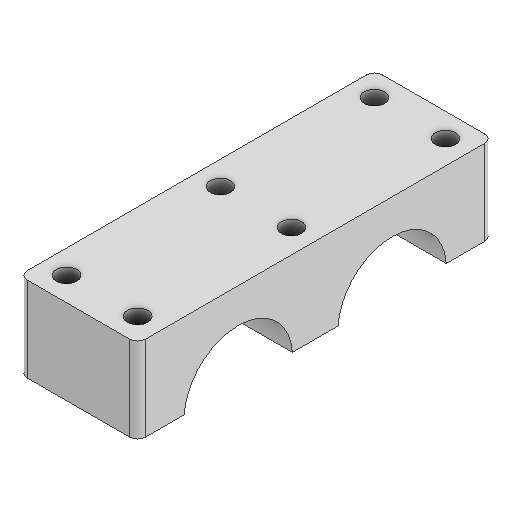
# Autodesk Inventor part: 3DP_PLA_A_Axis_Rotating_Stage_Fiberglass_pipes_mount_clamp
Saved by Autodesk Inventor 2027 (Build 310192060, 192F)
## iProperties
Created: 2026-01-07
Part Number: 3DP_PLA_A_Axis_Rotating_Stage_Fiberglass_pipes_mount_clamp
Material: Generic
Document SubType Name: Modeling
Designer: User
Density: 1 g/cm^3
Appearance: Default
Author: User
Autodesk Inventor part; units mm, degrees
ref_plane "YZ Plane" through (0, 0, 0) normal (1, 0, 0) x (0, 1, 0)
ref_plane "XZ Plane" through (0, 0, 0) normal (0, 1, 0) x (-1, 0, 0)
ref_plane "XY Plane" through (0, 0, 0) normal (0, 0, 1) x (1, 0, 0)
sketch "Sketch1" plane through (0, 0, 0) normal (0, 1, 0) x (-1, 0, 0)
  line L0 (15, 45) -> (-15, 45)
  line L1 (-15, 45) -> (-15, -45)
  line L2 (-15, -45) -> (15, -45)
  line L3 (15, -45) -> (15, 45)
  point P0 (0, 0)
  point P1 (9, 39)
  point P2 (-9, 39)
  point P3 (9, 0)
  point P4 (-9, 0)
  point P5 (9, -39)
  point P6 (-9, -39)
  dimension "d0" = 90
  dimension "d1" = 30
  dimension "d2" = 15
  dimension "d3" = 45
  dimension "d4" = 6
  dimension "d5" = 6
  dimension "d6" = 39
  dimension "d7" = 6
  dimension "d8" = 6
  constraints: 8 end point, 4 vertical alignment, 3 horizontal alignment, 2 parallel, 1 horizontal, 1 perpendicular
  measures "d0" distance between parallel lines of L2 L0
  measures "d1" distance between parallel lines of L1 L3
  measures "d2" distance from line of L3 point (0, 0)
  measures "d3" distance from line of L0 point (0, 0)
  measures "d4" distance from line of L0 point (-9, 39)
  measures "d5" distance from line of L2 point (-9, -39)
  measures "d6" distance of point (-9, 0) point (-9, 39)
  measures "d7" distance from line of L1 point (-9, 39)
  measures "d8" distance from line of L3 point (9, 39)
extrude "Extrusion1" add sketch "Sketch1" along normal blind 21.5
hole "Hole1" at (-9, 0, 39) at (9, 0, 39) at (-9, 0, 0) at (9, 0, 0) at (-9, 0, -39) at (9, 0, -39) direction (0, 1, 0) diameter 5.2 end through all
sketch "Sketch2" plane through (15, 0, 45) normal (1, 0, 0) x (0, 0, -1)
  line L0 (0, 0) -> (90, 0) projected
  line L1 (90, 0) -> (90, 21.5) projected
  line L2 (0, 21.5) -> (90, 21.5) projected
  line L3 (0, 0) -> (0, 21.5) projected
  circle A0 centre (25.5, -1) radius 13.75
  circle A1 centre (64.5, -1) radius 13.75
  line L4 (0, 0) -> (90, 0) projected
  point P0 (45, 0)
  point P1 (45, 0)
  point P2 (45, 0)
  point P3 (45, 0)
  dimension "d18" = 27.5
  dimension "d19" = 27.5
  dimension "d20" = 90
  dimension "d21" = 45
  dimension "d22" = 19.5
  dimension "d23" = 19.5
  dimension "d24" = 1
  constraints: 3 midpoint, 2 centre point, 1 horizontal alignment
  measures "d18" diameter of A0
  measures "d19" diameter of A1
  measures "d20" distance between parallel lines of L1 L3
  measures "d21" distance from line of point (45, 0) L3
  measures "d22" horizontal distance of point (45, 0) A0.centre
  measures "d23" horizontal distance of point (45, 0) A1.centre
  measures "d24" distance from line of L0 A0.centre
extrude "Extrusion2" cut sketch "Sketch2" against normal through all contours A0 L0 | L0 A0 | A1 L0 | L0 A1
fillet "Fillet1" radius 2 4 edges at (15, 10.75, 45) (-15, 10.75, 45) (15, 10.75, -45) (-15, 10.75, -45)
equation "\"d2\" = 0.5 * d1"
equation "\"d3\" = 0.5 * d0"
equation "\"d5\" = d4"
equation "\"d23\" = d22"
body "Solid1"
